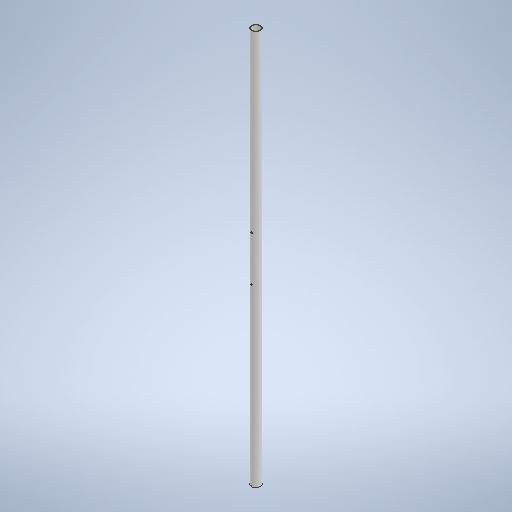
# Autodesk Inventor part: 88mm碳杆
Saved by Autodesk Inventor 2025 (Build 290162000, 162)
## iProperties
Created: 2026-11-18
Part Number: 88mm碳杆
Material: 常规
Document SubType Name: Modeling
Designer: ylh00
Density: 1 g/cm^3
Appearance: 默认
Author: ylh00
Autodesk Inventor part; units mm, degrees
ref_plane "YZ Plane" through (0, 0, 0) normal (1, 0, 0) x (0, 1, 0)
ref_plane "XZ Plane" through (0, 0, 0) normal (0, 1, 0) x (-1, 0, 0)
ref_plane "XY Plane" through (0, 0, 0) normal (0, 0, 1) x (1, 0, 0)
sketch "草图1" plane through (0, 0, 0) normal (0, 1, 0) x (-1, 0, 0)
  circle A0 centre (0, 0) radius 10
  circle A1 centre (0, 0) radius 9
  dimension "d0" = 20
  dimension "d1" = 18
  constraints: 2 centre point, 2 coincident
  measures "d0" diameter of A0
  measures "d1" diameter of A1
extrude "拉伸1" add sketch "草图1" along normal blind 880
sketch "草图2" plane through (0, 0, 0) normal (0, 0, 1) x (1, 0, 0)
  line L0 (-10, 0) -> (-10, 880) projected
  line L1 (-10, 440) -> (10, 440)
  line L2 (10, 0) -> (10, 880) projected
  line L3 (0, 440) -> (0, 490)
  line L4 (0, 490) -> (0, 390)
  circle A0 centre (0, 490) radius 1.6
  circle A1 centre (0, 390) radius 1.6
  point P0 (0, 0)
  dimension "d4" = 50
  dimension "d5" = 100
  dimension "d6" = 3.2
  dimension "d7" = 3.2
  constraints: 6 end point, 3 midpoint, 2 centre point, 2 coincident, 1 point on line, 1 vertical
  measures "d4" distance of L3.start L3.end
  measures "d5" distance of L3.end L4.end
  measures "d6" diameter of A0
  measures "d7" diameter of A1
extrude "拉伸2" cut sketch "草图2" along normal mid plane 880
